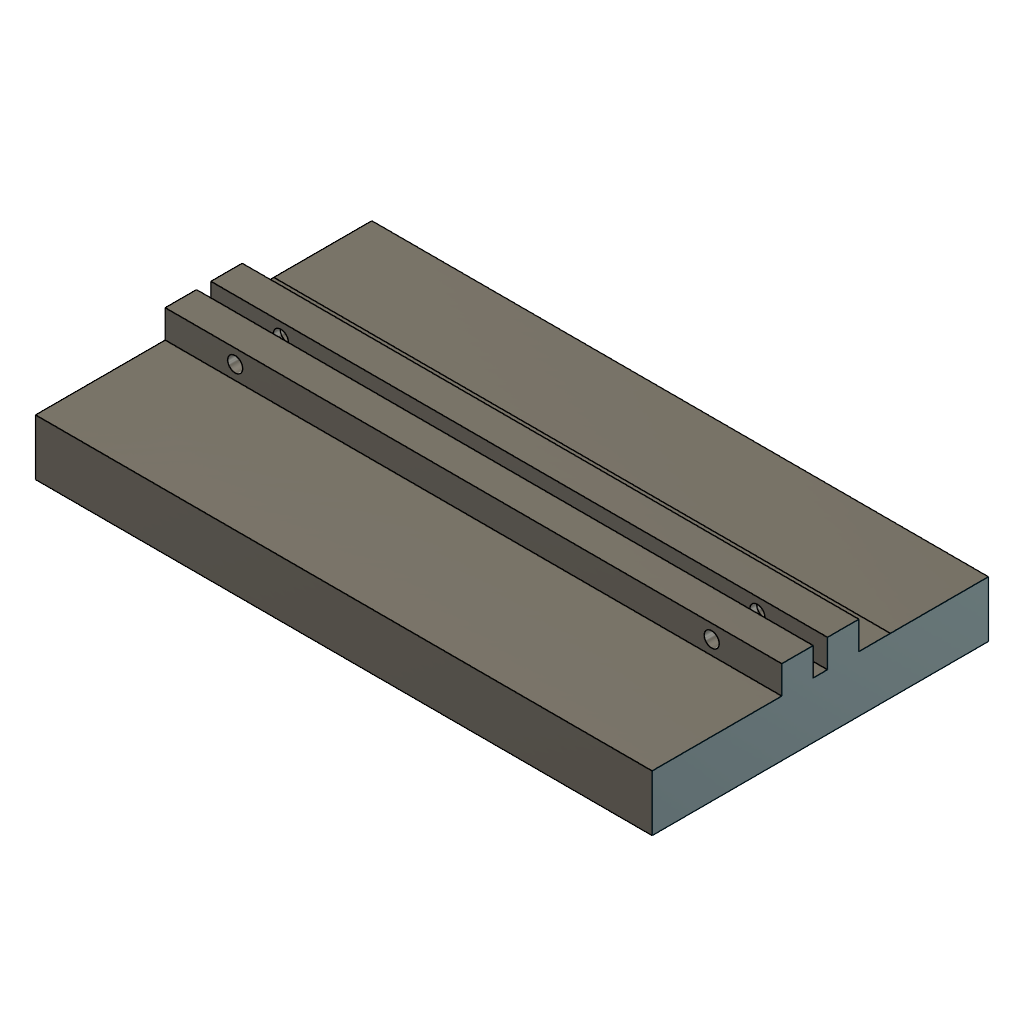
ground_2 (Autodesk Fusion 360 design; units mm, degrees)
part number: 2026-11-18-20-15-48-038
Autodesk Fusion 360 part; units mm, degrees
sketch "Sketch1" plane through (0, 0, 0) normal (0, 1, 0) x (1, 0, 0)
  line L0 (-110, 60) -> (110, 60)
  line L1 (110, 60) -> (110, -60)
  line L2 (110, -60) -> (-110, -60)
  line L3 (-110, -60) -> (-110, 60)
  dimension "d1" = 220
  dimension "d2" = 110
  dimension "d3" = 60
  dimension "d4" = 60
  constraint horizontal L0
  constraint vertical L1
  constraint horizontal L2
  constraint vertical L3
  measures "d1" distance of L0.start L0.end
  measures "d2" distance of origin L1
  measures "d3" distance of origin L0
  measures "d4" distance of origin L2
extrude "Extrude1" add sketch "Sketch1" along normal blind 20
sketch "Sketch2" plane through (0, 20, 0) normal (0, 1, 0) x (-1, 0, 0)
  line L0 (110, 60) -> (-110, 60)
  line L1 (-110, 60) -> (-110, -60)
  line L2 (-110, -60) -> (110, -60)
  line L3 (110, -60) -> (110, 60)
  line L4 (110, -60) -> (110, -5)
  line L5 (-110, -5) -> (-110, -25)
  line L6 (110, -5) -> (-110, -5)
  line L7 (110, -25) -> (-110, -25)
  line L8 (110, -5) -> (110, 5)
  line L9 (110, 5) -> (110, 25)
  line L10 (110, 25) -> (-110, 25)
  line L11 (-110, 25) -> (-110, 5)
  line L12 (-110, 5) -> (110, 5)
  dimension "d7" = 10
  constraint coincident L2.end L3.start
  constraint coincident L3 L4.end
  constraint coincident L1 L5.start
  constraint coincident L1 L5.end
  constraint perpendicular L5 L6
  constraint coincident L4 L7.start
  constraint perpendicular L5 L7
  constraint coincident L3 L8.end
  constraint coincident L3 L9.end
  constraint coincident L1 L10.end
  constraint perpendicular L1 L10
  constraint coincident L1 L11.end
  constraint perpendicular L9 L12
  measures "d7" distance of L6 L12
extrude "Extrude2" add sketch "Sketch2" along normal blind 20 contours L1 L3 L9 L10 L11 L12 | L1 L3 L4 L5 L6 L7
sketch "Sketch3" plane through (0, 0, 25) normal (0, 0, 1) x (1, 0, 0)
  line L0 (-110, 20) -> (110, 20)
  line L1 (110, 20) -> (110, 40)
  line L2 (110, 40) -> (-110, 40)
  line L3 (-110, 40) -> (-110, 20)
  circle A0 centre (100, 25) radius 2.7
  circle A1 centre (-100, 25) radius 2.7
  dimension "d10" = 5.4
  dimension "d11" = 10
  dimension "d12" = 5
  dimension "d13" = 5.4
  dimension "d14" = 10
  dimension "d15" = 5
  dimension "d16" = 200
  dimension "d19" = 200
  measures "d10" diameter of A0
  measures "d11" distance of L1 A0.centre
  measures "d12" distance of L0 A0.centre
  measures "d13" diameter of A1
  measures "d14" distance of L3 A1.centre
  measures "d15" distance of L0 A1.centre
  measures "d16" distance of A0.centre A1.centre
  measures "d19" distance of A0.centre A1.centre
extrude "Extrude3" add sketch "Sketch3" along normal blind 1 contours A0 | A1
extrude "Extrude4" cut 2 faces at (-99.1773, 25.7633, 26) (100.8227, 25.7633, 26) along direction (0, 0, -1) blind 1
sketch "Sketch4" plane through (0, 0, 25) normal (0, 0, 1) x (1, 0, 0)
  line L0 (-110, 20) -> (110, 20)
  line L1 (110, 20) -> (110, 40)
  line L2 (110, 40) -> (-110, 40)
  line L3 (-110, 40) -> (-110, 20)
  circle A0 centre (-85, 25) radius 2.7
  circle A1 centre (85, 25) radius 2.7
  dimension "d22" = 5.4
  dimension "d23" = 5
  dimension "d24" = 5.4
  dimension "d25" = 5
  dimension "d26" = 170
  dimension "d27" = 25
  dimension "d28" = 25
  measures "d22" diameter of A0
  measures "d23" distance of L0 A0.centre
  measures "d24" diameter of A1
  measures "d25" distance of L0 A1.centre
  measures "d26" distance of A0.centre A1.centre
  measures "d27" distance of L1 A1.centre
  measures "d28" distance of L3 A0.centre
extrude "Extrude5" cut sketch "Sketch4" against normal blind 250 contours A0 | A1
extrude "Extrude6" cut 2 faces at (36.6667, 40, 18.3333) (-36.6667, 40, -11.6667) along direction (0, -1, 0) blind 10
sketch "Sketch5" plane through (0, 20, 0) normal (0, 1, 0) x (-1, 0, 0)
  line L0 (-110, -5) -> (110, -5)
  line L1 (110, -5) -> (110, 5)
  line L2 (110, 5) -> (-110, 5)
  line L3 (-110, 5) -> (-110, -5)
  line L4 (-110, 5) -> (-110, 2.5)
  line L5 (-110, -5) -> (-110, -2.5)
  line L6 (-110, 2.5) -> (110, 2.5)
  line L7 (110, 2.5) -> (110, 5)
  line L8 (110, -5) -> (110, -2.5)
  line L9 (110, -2.5) -> (-110, -2.5)
  dimension "d33" = 2.5
  dimension "d34" = 2.5
  dimension "d35" = 2.5
  constraint coincident L2.end L3.start
  constraint perpendicular L2 L4
  constraint coincident L0.start L3.end
  constraint perpendicular L0 L5
  constraint coincident L1 L6.end
  constraint perpendicular L1 L6
  constraint coincident L1.end L2.start
  constraint coincident L0.end L1.start
  constraint perpendicular L0 L8
  measures "d33" distance of L2.end L4.end
  measures "d34" distance of L0.start L5.end
  measures "d35" distance of L0.end L8.end
extrude "Extrude7" add sketch "Sketch5" along normal blind 10 contours L0 L1 L3 L5 L8 L9 | L1 L2 L3 L4 L6 L7
sketch "Sketch6" plane through (0, 0, -2.5) normal (0, 0, 1) x (1, 0, 0)
  line L0 (-110, 20) -> (110, 20)
  line L1 (110, 20) -> (110, 30)
  line L2 (110, 30) -> (-110, 30)
  line L3 (-110, 30) -> (-110, 20)
  circle A0 centre (85, 25) radius 2.7
  circle A1 centre (-85, 25) radius 2.7
  dimension "d38" = 5.4
  dimension "d39" = 5.4
  measures "d38" diameter of A0
  measures "d39" diameter of A1
extrude "Extrude8" cut sketch "Sketch6" against normal blind 120 contours A0 | A1
sketch "Sketch7" plane through (0, 0, 2.5) normal (0, 0, -1) x (-1, 0, 0)
  line L0 (-110, 20) -> (110, 20)
  line L1 (110, 20) -> (110, 30)
  line L2 (110, 30) -> (-110, 30)
  line L3 (-110, 30) -> (-110, 20)
  circle A0 centre (-85, 25) radius 2.7
  circle A1 centre (85, 25) radius 2.7
  dimension "d42" = 5.4
  dimension "d43" = 5.4
  measures "d42" diameter of A0
  measures "d43" diameter of A1
sketch "Sketch8" plane through (0, 30, 0) normal (0, 1, 0) x (-1, 0, 0)
  line L0 (110, 2.5) -> (110, 25)
  line L1 (110, 25) -> (-110, 25)
  line L2 (-110, 25) -> (-110, 2.5)
  line L3 (-110, 2.5) -> (110, 2.5)
  line L4 (110, 2.5) -> (110, 13.75)
  line L5 (110, 13.75) -> (-110, 13.75)
  line L6 (-110, 2.5) -> (-110, 13.75)
  line L7 (110, -2.5) -> (110, -13.75)
  dimension "d44" = 11.25
  constraint coincident L0.start L3.end
  constraint midpoint L0 L4.end
  constraint midpoint L2 L5.end
  constraint coincident L2.end L3.start
  constraint vertical L7
  measures "d44" distance of L7.start L7.end
extrude "Extrude9" cut sketch "Sketch8" against normal blind 10 contours L0 L1 L2 L5
sketch "Sketch9" plane through (110, 0, 0) normal (1, 0, 0) x (0, 0, -1)
  line L0 (-13.75, 20) -> (-60, 20)
  line L1 (-60, 20) -> (-60, 0)
  line L2 (-60, 0) -> (60, 0)
  line L3 (60, 0) -> (60, 20)
  line L4 (60, 20) -> (25, 20)
  line L5 (25, 20) -> (25, 30)
  line L6 (25, 30) -> (2.5, 30)
  line L7 (2.5, 30) -> (2.5, 20)
  line L8 (2.5, 20) -> (-2.5, 20)
  line L9 (-2.5, 20) -> (-2.5, 30)
  line L10 (-2.5, 30) -> (-13.75, 30)
  line L11 (-13.75, 30) -> (-13.75, 20)
  line L12 (2.5, 30) -> (13.75, 30)
  line L13 (13.75, 30) -> (13.75, 20)
  line L14 (13.75, 20) -> (2.5, 20)
  line L15 (2.5, 20) -> (2.5, 30)
  line L16 (13.75, 20) -> (25, 20)
  dimension "d47" = 11.25
  dimension "d48" = 11.25
  constraint coincident L6.end L7.start
  constraint perpendicular L7 L12
  constraint perpendicular L12 L13
  constraint coincident L7.end L8.start
  constraint coincident L4.end L5.start
  measures "d47" distance of L9.end L10.end
  measures "d48" distance of L6.end L12.end
extrude "Extrude10" cut sketch "Sketch9" against normal blind 280 contours L5 L6 L13 L16
sketch "Sketch10" plane through (110, 0, 0) normal (1, 0, 0) x (0, 0, -1)
  line L0 (13.75, 20) -> (13.75, 30)
  line L1 (13.75, 30) -> (2.5, 30)
  line L2 (2.5, 30) -> (2.5, 20)
  line L3 (2.5, 20) -> (-2.5, 20)
  line L4 (-2.5, 20) -> (-2.5, 30)
  line L5 (-2.5, 30) -> (-13.75, 30)
  line L6 (-13.75, 30) -> (-13.75, 20)
  line L7 (-13.75, 20) -> (-60, 20)
  line L8 (-60, 20) -> (-60, 0)
  line L9 (-60, 0) -> (60, 0)
  line L10 (60, 0) -> (60, 20)
  line L11 (60, 20) -> (25, 20)
  line L12 (25, 20) -> (13.75, 20)
  dimension "d51" = 5
  measures "d51" distance of L2.end L3.end
sketch "Sketch11" plane through (110, 0, 0) normal (1, 0, 0) x (0, 0, -1)
  line L0 (-2.5, 30) -> (-2.55, 30)
  line L1 (-2.55, 30) -> (-2.55, 20)
  line L2 (-2.55, 20) -> (-2.5, 20)
  line L3 (-2.5, 20) -> (-2.5, 30)
  dimension "d52" = 0.05
  constraint horizontal L0
  constraint perpendicular L0 L1
  constraint perpendicular L1 L2
  constraint perpendicular L0 L3
  measures "d52" distance of L0.start L0.end
extrude "Extrude11" cut sketch "Sketch11" against normal blind 280
extrude "Extrude12" cut sketch "Sketch7" against normal blind 45 contours A0 | A1
sketch "Sketch12" plane through (110, 0, 0) normal (1, 0, 0) x (0, 0, -1)
  line L0 (2.5, 30) -> (2.55, 30)
  line L1 (2.55, 30) -> (2.55, 20)
  line L2 (2.5, 20) -> (2.5, 30)
  line L3 (2.5, 20) -> (2.55, 20)
  dimension "d57" = 0.05
  constraint horizontal L0
  constraint perpendicular L0 L1
  constraint perpendicular L0 L2
  constraint perpendicular L1 L3
  measures "d57" distance of L0.start L0.end
extrude "Extrude13" cut sketch "Sketch12" against normal blind 280
